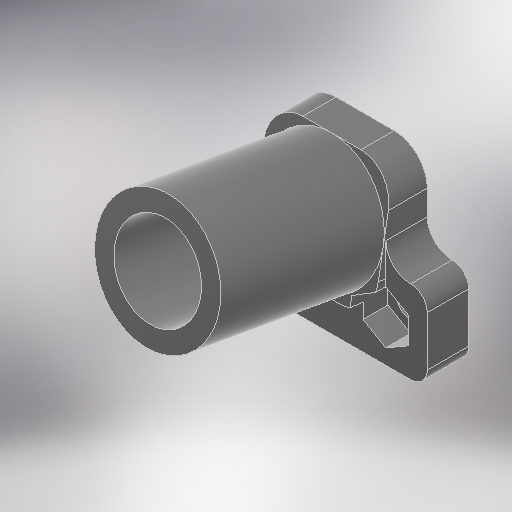
# Autodesk Inventor part: 3D_carbon_mount-base
Saved by Autodesk Inventor 2025.3 (Build 293356030, 356C)
## iProperties
Created: 2026-09-02
Part Number: 3D_carbon_mount-base
Material: 一般
Document SubType Name: Modeling
Designer: ibuki_ono
Density: 1 g/cm^3
Appearance: 滑らか - 黒
Author: ibuki_ono
## iProperties of the stored document 3D_carbon_mount-base_3D プリント.ipt
Created: 2026-09-04
Part Number: 3D_carbon_mount-base_3D プリント
Material: 一般
Document SubType Name: Modeling
Designer: ibuki_ono
Density: 1 g/cm^3
Appearance: 既定
Author: ibuki_ono
Autodesk Inventor part; units mm, degrees
ref_plane "YZ Plane" through (0, 0, 0) normal (1, 0, 0) x (0, 1, 0)
ref_plane "XZ Plane" through (0, 0, 0) normal (0, 1, 0) x (-1, 0, 0)
ref_plane "XY Plane" through (0, 0, 0) normal (0, 0, 1) x (1, 0, 0)
sketch "スケッチ1" plane through (0, 0, 0) normal (0, 0, 1) x (1, 0, 0)
  line L0 (12.5, -5) -> (-12.5, -5)
  line L1 (-12.5, -5) -> (-12.5, 5)
  line L2 (-12.5, 5) -> (12.5, 5)
  line L3 (12.5, 5) -> (12.5, -5)
  line L4 (12.5, -5) -> (-12.5, 5) construction
  line L5 (-12.5, -5) -> (12.5, 5) construction
  point P0 (0, 0)
  dimension "d0" = 25
  dimension "d1" = 10
  constraints: 12 end point, 2 midpoint, 2 parallel, 1 horizontal, 1 perpendicular
  measures "d0" distance of L1.end L2.end
  measures "d1" distance of L0.end L1.end
extrude "押し出し1" add sketch "スケッチ1" along normal blind 5
sketch "スケッチ2" plane through (0, 0, 0) normal (1, 0, 0) x (0, 1, 0)
  line L0 (5, 0) -> (5, 5) projected
  line L1 (-5, 5) -> (5, 5) projected
  line L2 (5, 0) -> (-5, 0) projected
  line L3 (5, 0) -> (15, 0)
  line L4 (5, 0) -> (15, 0) construction
  line L5 (15, 0) -> (15, 4)
  line L6 (15, 4) -> (0.2279, 6.6047)
  line L7 (0.2279, 6.6047) -> (0, 5)
  point P0 (0, 0)
  dimension "d4" = 10
  dimension "d5" = 0
  dimension "d6" = 4
  dimension "d7" = 90
  dimension "d8" = 15
  dimension "d9" = 100
  constraints: 10 end point, 2 horizontal, 1 collinear, 1 midpoint, 1 perpendicular
  measures "d4" distance of L0.start L3.end
  measures "d5" distance between parallel lines of L3 L4
  measures "d6" distance of L3.end L5.end
  measures "d7" angle of L5 L3
  measures "d8" distance of L5.end L6.end
  measures "d9" angle of L6 L5
extrude "押し出し2" add sketch "スケッチ2" along normal mid plane 15
sketch "スケッチ3" plane through (-7.5, 0.2279, 6.6047) normal (0, 0.1736482, 0.9848078) x (1, 0, 0)
  line L0 (15, 0) -> (0, 0) projected
  line L1 (15, 15) -> (15, 0) projected
  line L2 (0, 15) -> (15, 15) projected
  line L3 (0, 0) -> (0, 15) projected
  line L4 (0, 15) -> (15, 15) construction
  line L5 (15, 0.0542) -> (0, 0.0542) construction
  circle A0 centre (7.5, 7.5) radius 7.5
  circle A1 centre (7.5, 7.5) radius 5.2
  line L6 (7.5, 15) -> (7.5, 0) construction
  line L7 (15, 0) -> (0, 0) construction
  line L8 (0, 0) -> (0, 15) projected
  point P0 (7.5, 0.9225)
  point P1 (8.4525, 0)
  point P2 (7.5, 0)
  point P3 (0, 7.5)
  dimension "d12" = 10.4
  constraints: 3 midpoint, 2 centre point, 2 coincident, 2 end point, 2 tangent
  measures "d12" diameter of A1
extrude "押し出し3" add sketch "スケッチ3" along normal blind 20 contours A0
fillet "フィレット1" radius 4 4 edges at (7.5, 0.1139, 5.8024) (-7.5, 0.1139, 5.8024) (7.5, 15, 2) (-7.5, 15, 2)
sketch "スケッチ4" plane through (0, 0, 5) normal (0, 0, 1) x (1, 0, 0)
  line L0 (-12.5, 5) -> (-12.5, -5) projected
  line L1 (12.5, -5) -> (12.5, 5) projected
  line L2 (-12.5, 0) -> (12.5, 0) construction
  line L3 (3.5, 0) -> (-3.5, 0) projected
  point P0 (0, 0)
  point P1 (-7.5, 0)
  point P2 (7.5, 0)
  point P3 (0, 0)
  point P4 (0, 0)
  dimension "d16" = 7.5
  dimension "d17" = 7.5
  constraints: 4 midpoint, 2 end point, 2 point on line
  measures "d16" distance of point (0, 0) point (-7.5, 0)
  measures "d17" distance of point (0, 0) point (7.5, 0)
hole "穴1" at (-7.5, 0, 5) at (7.5, 0, 5) direction (0, 0, -1) diameter 3.5 end through all
sketch "スケッチ5" plane through (0, 0, 5) normal (0, 0, 1) x (1, 0, 0)
  arc A0 (-6.6211, 1.5133) -> (-5.9832, 0.8728) centre (-7.5, 0) ccw projected
  arc A1 (5.9832, 0.8728) -> (6.6211, 1.5133) centre (7.5, 0) ccw projected
  line L0 (-7.5, 3.1754) -> (-4.75, 1.5877)
  line L1 (-4.75, 1.5877) -> (-4.75, -1.5877)
  line L2 (-4.75, -1.5877) -> (-7.5, -3.1754)
  line L3 (-7.5, -3.1754) -> (-10.25, -1.5877)
  line L4 (-10.25, -1.5877) -> (-10.25, 1.5877)
  line L5 (-10.25, 1.5877) -> (-7.5, 3.1754)
  line L6 (7.5, -3.1754) -> (4.75, -1.5877)
  line L7 (4.75, -1.5877) -> (4.75, 1.5877)
  line L8 (4.75, 1.5877) -> (7.5, 3.1754)
  line L9 (7.5, 3.1754) -> (10.25, 1.5877)
  line L10 (10.25, 1.5877) -> (10.25, -1.5877)
  line L11 (10.25, -1.5877) -> (7.5, -3.1754)
  point P0 (0, 0)
  dimension "d25" = 5.5
  dimension "d26" = 5.5
  constraints: 24 end point, 2 coincident, 2 vertical alignment, 26 other
  measures "d25" distance between parallel lines of L1 L4
  measures "d26" distance between parallel lines of L10 L7
extrude "押し出し4" cut sketch "スケッチ5" along normal blind 5 and the other way blind 3
fillet "フィレット2" radius 2 4 edges at (-12.5, -5, 2.5) (-12.5, 5, 2.5) (12.5, 5, 2.5) (12.5, -5, 2.5)
fillet "フィレット4" radius 3 2 edges at (7.5, 5, 2.5) (-7.5, 5, 2.5)
equation "\"d17\" = d16"
equation "\"d26\" = d25"
